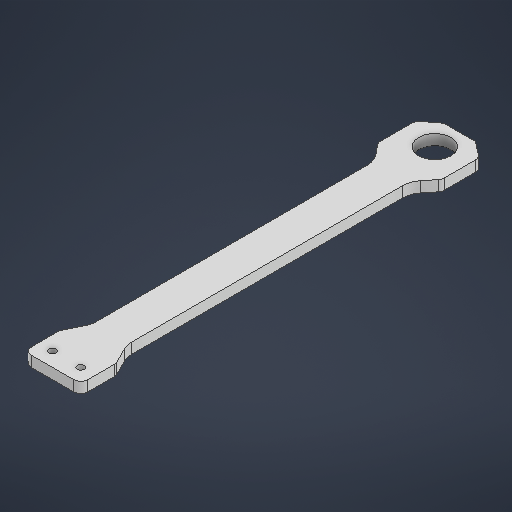
# Autodesk Inventor part: thanhlk 3
Saved by Autodesk Inventor 2027 (Build 310192060, 192F)
## iProperties
Created: 2026-08-21
Part Number: thanhlk 3
Material: Generic
Document SubType Name: Modeling
Designer: thita
Density: 1 g/cm^3
Appearance: Default
Author: thita
Autodesk Inventor part; units mm, degrees
ref_plane "YZ Plane" through (0, 0, 0) normal (1, 0, 0) x (0, 1, 0)
ref_plane "XZ Plane" through (0, 0, 0) normal (0, 1, 0) x (-1, 0, 0)
ref_plane "XY Plane" through (0, 0, 0) normal (0, 0, 1) x (1, 0, 0)
sketch "Sketch1" plane through (0, 0, 0) normal (0, 1, 0) x (-1, 0, 0)
  arc A0 (-8, 98.4721) -> (-7.7889, 97.5777) centre (-6, 98.4721) ccw
  line L0 (-7.7889, 97.5777) -> (-5.6334, 93.2669)
  arc A1 (-5, 90.5836) -> (-5.6334, 93.2669) centre (-11, 90.5836) ccw
  line L1 (-5, 90.5836) -> (-5, 14.1047)
  arc A2 (-6.3148, 10.3565) -> (-5, 14.1047) centre (-11, 14.1047) ccw
  line L2 (-6.3148, 10.3565) -> (-8.5617, 7.5478)
  arc A3 (-8.5617, 7.5478) -> (-9, 6.2984) centre (-7, 6.2984) ccw
  line L3 (-9, 6.2984) -> (-9, -2.5218)
  arc A4 (-9, -2.5218) -> (-8.2279, -4.1005) centre (-7, -2.5218) ccw
  line L4 (-8.2279, -4.1005) -> (-4.5, -7)
  line L5 (-4.5, -7) -> (4.5, -7)
  line L6 (4.5, -7) -> (8.2279, -4.1005)
  arc A5 (8.2279, -4.1005) -> (9, -2.5218) centre (7, -2.5218) ccw
  line L7 (9, -2.5218) -> (9, 6.2984)
  arc A6 (9, 6.2984) -> (8.5617, 7.5478) centre (7, 6.2984) ccw
  line L8 (8.5617, 7.5478) -> (6.3148, 10.3565)
  arc A7 (5, 14.1047) -> (6.3148, 10.3565) centre (11, 14.1047) ccw
  line L9 (5, 14.1047) -> (5, 90.5836)
  arc A8 (5.6334, 93.2669) -> (5, 90.5836) centre (11, 90.5836) ccw
  line L10 (5.6334, 93.2669) -> (7.7889, 97.5777)
  arc A9 (7.7889, 97.5777) -> (8, 98.4721) centre (6, 98.4721) ccw
  line L11 (8, 98.4721) -> (8, 106)
  arc A10 (8, 106) -> (6, 108) centre (6, 106) ccw
  line L12 (6, 108) -> (-6, 108)
  arc A11 (-6, 108) -> (-8, 106) centre (-6, 106) ccw
  line L13 (-8, 106) -> (-8, 98.4721)
  circle A12 centre (-4, 104) radius 1
  circle A13 centre (4, 104) radius 1
  arc A14 (3, 2.6458) -> (-3, 2.6458) centre (0, 0) ccw
  arc A15 (-3, -2.6458) -> (3, -2.6458) centre (0, 0) ccw
  circle A16 centre (0, 0) radius 4.55
  point P0 (0, 0)
  dimension "d1" = 9.1
  constraints: 28 end point, 28 point on circle, 17 centre point
  measures "d1" diameter of A16
extrude "Extrusion1" add sketch "Sketch1" along normal blind 3
body "Solid1"
